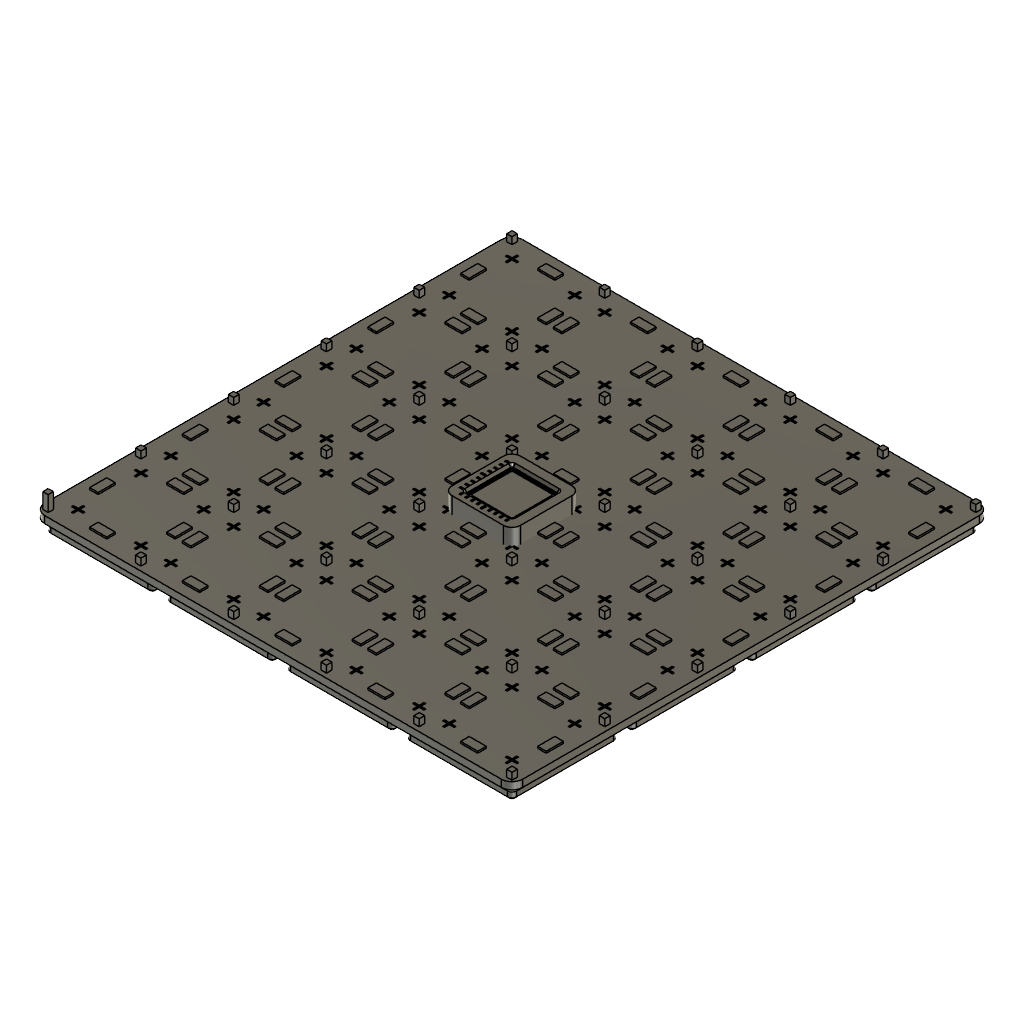
da-lab3-tilgaplaat-atoms3-mudel (Autodesk Fusion 360 design; units mm, degrees)
part number: 2026-11-13-17-36-51-627
part number: 2026-11-13-17-36-56-494
part number: 2026-11-13-17-37-25-971
Autodesk Fusion 360 part; units mm, degrees
(part 1 of 3)
ref_plane "WorkPlane1" through (0, 0, 4.75) normal (0, 0, 1) x (1, 0, 0) in component "drop_plate"
sketch "plate" plane through (0, 0, 4.75) normal (0, 0, 1) x (1, 0, 0) in component "drop_plate"
  line L0 (-80, -83.75) -> (80, -83.75)
  line L1 (83.75, -80) -> (83.75, 80)
  line L2 (80, 83.75) -> (-80, 83.75)
  line L3 (-83.75, 80) -> (-83.75, -80)
  arc A0 (80, -83.75) -> (83.75, -80) centre (80, -80) ccw
  arc A1 (83.75, 80) -> (80, 83.75) centre (80, 80) ccw
  arc A2 (-80, 83.75) -> (-83.75, 80) centre (-80, 80) ccw
  arc A3 (-83.75, -80) -> (-80, -83.75) centre (-80, -80) ccw
  constraint tangent L0 A0
  constraint tangent L1 A0
  constraint tangent L1 A1
  constraint tangent L2 A1
  constraint tangent L2 A2
  constraint tangent L3 A2
  constraint tangent L3 A3
  constraint tangent L0 A3
extrude "plate (1)" add sketch "plate" along normal blind 2.5 makes body 1 in component "drop_plate"
ref_plane "WorkPlane2" through (0, 0, 4.75) normal (0, 0, 1) x (1, 0, 0) in component "drop_plate"
sketch "gf_std_foot1" plane through (0, 0, 4.75) normal (0, 0, 1) x (1, 0, 0) in component "drop_plate"
  line L0 (-46, -42.25) -> (-80, -42.25)
  line L1 (-83.75, -46) -> (-83.75, -80)
  line L2 (-80, -83.75) -> (-46, -83.75)
  line L3 (-42.25, -80) -> (-42.25, -46)
  arc A0 (-80, -42.25) -> (-83.75, -46) centre (-80, -46) ccw
  arc A1 (-83.75, -80) -> (-80, -83.75) centre (-80, -80) ccw
  arc A2 (-46, -83.75) -> (-42.25, -80) centre (-46, -80) ccw
  arc A3 (-42.25, -46) -> (-46, -42.25) centre (-46, -46) ccw
  line L4 (-46, -0.25) -> (-80, -0.25)
  line L5 (-83.75, -4) -> (-83.75, -38)
  line L6 (-80, -41.75) -> (-46, -41.75)
  line L7 (-42.25, -38) -> (-42.25, -4)
  arc A4 (-80, -0.25) -> (-83.75, -4) centre (-80, -4) ccw
  arc A5 (-83.75, -38) -> (-80, -41.75) centre (-80, -38) ccw
  arc A6 (-46, -41.75) -> (-42.25, -38) centre (-46, -38) ccw
  arc A7 (-42.25, -4) -> (-46, -0.25) centre (-46, -4) ccw
  line L8 (-46, 41.75) -> (-80, 41.75)
  line L9 (-83.75, 38) -> (-83.75, 4)
  line L10 (-80, 0.25) -> (-46, 0.25)
  line L11 (-42.25, 4) -> (-42.25, 38)
  arc A8 (-80, 41.75) -> (-83.75, 38) centre (-80, 38) ccw
  arc A9 (-83.75, 4) -> (-80, 0.25) centre (-80, 4) ccw
  arc A10 (-46, 0.25) -> (-42.25, 4) centre (-46, 4) ccw
  arc A11 (-42.25, 38) -> (-46, 41.75) centre (-46, 38) ccw
  line L12 (-46, 83.75) -> (-80, 83.75)
  line L13 (-83.75, 80) -> (-83.75, 46)
  line L14 (-80, 42.25) -> (-46, 42.25)
  line L15 (-42.25, 46) -> (-42.25, 80)
  arc A12 (-80, 83.75) -> (-83.75, 80) centre (-80, 80) ccw
  arc A13 (-83.75, 46) -> (-80, 42.25) centre (-80, 46) ccw
  arc A14 (-46, 42.25) -> (-42.25, 46) centre (-46, 46) ccw
  arc A15 (-42.25, 80) -> (-46, 83.75) centre (-46, 80) ccw
  line L16 (-4, -42.25) -> (-38, -42.25)
  line L17 (-41.75, -46) -> (-41.75, -80)
  line L18 (-38, -83.75) -> (-4, -83.75)
  line L19 (-0.25, -80) -> (-0.25, -46)
  arc A16 (-38, -42.25) -> (-41.75, -46) centre (-38, -46) ccw
  arc A17 (-41.75, -80) -> (-38, -83.75) centre (-38, -80) ccw
  arc A18 (-4, -83.75) -> (-0.25, -80) centre (-4, -80) ccw
  arc A19 (-0.25, -46) -> (-4, -42.25) centre (-4, -46) ccw
  line L20 (-4, -0.25) -> (-38, -0.25)
  line L21 (-41.75, -4) -> (-41.75, -38)
  line L22 (-38, -41.75) -> (-4, -41.75)
  line L23 (-0.25, -38) -> (-0.25, -4)
  arc A20 (-38, -0.25) -> (-41.75, -4) centre (-38, -4) ccw
  arc A21 (-41.75, -38) -> (-38, -41.75) centre (-38, -38) ccw
  arc A22 (-4, -41.75) -> (-0.25, -38) centre (-4, -38) ccw
  arc A23 (-0.25, -4) -> (-4, -0.25) centre (-4, -4) ccw
  line L24 (-4, 41.75) -> (-38, 41.75)
  line L25 (-41.75, 38) -> (-41.75, 4)
  line L26 (-38, 0.25) -> (-4, 0.25)
  line L27 (-0.25, 4) -> (-0.25, 38)
  arc A24 (-38, 41.75) -> (-41.75, 38) centre (-38, 38) ccw
  arc A25 (-41.75, 4) -> (-38, 0.25) centre (-38, 4) ccw
  arc A26 (-4, 0.25) -> (-0.25, 4) centre (-4, 4) ccw
  arc A27 (-0.25, 38) -> (-4, 41.75) centre (-4, 38) ccw
  line L28 (-4, 83.75) -> (-38, 83.75)
  line L29 (-41.75, 80) -> (-41.75, 46)
  line L30 (-38, 42.25) -> (-4, 42.25)
  line L31 (-0.25, 46) -> (-0.25, 80)
  arc A28 (-38, 83.75) -> (-41.75, 80) centre (-38, 80) ccw
  arc A29 (-41.75, 46) -> (-38, 42.25) centre (-38, 46) ccw
  arc A30 (-4, 42.25) -> (-0.25, 46) centre (-4, 46) ccw
  arc A31 (-0.25, 80) -> (-4, 83.75) centre (-4, 80) ccw
  line L32 (38, -42.25) -> (4, -42.25)
  line L33 (0.25, -46) -> (0.25, -80)
  line L34 (4, -83.75) -> (38, -83.75)
  line L35 (41.75, -80) -> (41.75, -46)
  arc A32 (4, -42.25) -> (0.25, -46) centre (4, -46) ccw
  arc A33 (0.25, -80) -> (4, -83.75) centre (4, -80) ccw
  arc A34 (38, -83.75) -> (41.75, -80) centre (38, -80) ccw
  arc A35 (41.75, -46) -> (38, -42.25) centre (38, -46) ccw
  line L36 (38, -0.25) -> (4, -0.25)
  line L37 (0.25, -4) -> (0.25, -38)
  line L38 (4, -41.75) -> (38, -41.75)
  line L39 (41.75, -38) -> (41.75, -4)
  arc A36 (4, -0.25) -> (0.25, -4) centre (4, -4) ccw
  arc A37 (0.25, -38) -> (4, -41.75) centre (4, -38) ccw
  arc A38 (38, -41.75) -> (41.75, -38) centre (38, -38) ccw
  arc A39 (41.75, -4) -> (38, -0.25) centre (38, -4) ccw
  line L40 (38, 41.75) -> (4, 41.75)
  line L41 (0.25, 38) -> (0.25, 4)
  line L42 (4, 0.25) -> (38, 0.25)
  line L43 (41.75, 4) -> (41.75, 38)
  arc A40 (4, 41.75) -> (0.25, 38) centre (4, 38) ccw
  arc A41 (0.25, 4) -> (4, 0.25) centre (4, 4) ccw
  arc A42 (38, 0.25) -> (41.75, 4) centre (38, 4) ccw
  arc A43 (41.75, 38) -> (38, 41.75) centre (38, 38) ccw
  line L44 (38, 83.75) -> (4, 83.75)
  line L45 (0.25, 80) -> (0.25, 46)
  line L46 (4, 42.25) -> (38, 42.25)
  line L47 (41.75, 46) -> (41.75, 80)
  arc A44 (4, 83.75) -> (0.25, 80) centre (4, 80) ccw
  arc A45 (0.25, 46) -> (4, 42.25) centre (4, 46) ccw
  arc A46 (38, 42.25) -> (41.75, 46) centre (38, 46) ccw
  arc A47 (41.75, 80) -> (38, 83.75) centre (38, 80) ccw
  line L48 (80, -42.25) -> (46, -42.25)
  line L49 (42.25, -46) -> (42.25, -80)
  line L50 (46, -83.75) -> (80, -83.75)
  line L51 (83.75, -80) -> (83.75, -46)
  arc A48 (46, -42.25) -> (42.25, -46) centre (46, -46) ccw
  arc A49 (42.25, -80) -> (46, -83.75) centre (46, -80) ccw
  arc A50 (80, -83.75) -> (83.75, -80) centre (80, -80) ccw
  arc A51 (83.75, -46) -> (80, -42.25) centre (80, -46) ccw
  line L52 (80, -0.25) -> (46, -0.25)
  line L53 (42.25, -4) -> (42.25, -38)
  line L54 (46, -41.75) -> (80, -41.75)
  line L55 (83.75, -38) -> (83.75, -4)
  arc A52 (46, -0.25) -> (42.25, -4) centre (46, -4) ccw
  arc A53 (42.25, -38) -> (46, -41.75) centre (46, -38) ccw
  arc A54 (80, -41.75) -> (83.75, -38) centre (80, -38) ccw
  arc A55 (83.75, -4) -> (80, -0.25) centre (80, -4) ccw
  line L56 (80, 41.75) -> (46, 41.75)
  line L57 (42.25, 38) -> (42.25, 4)
  line L58 (46, 0.25) -> (80, 0.25)
  line L59 (83.75, 4) -> (83.75, 38)
  arc A56 (46, 41.75) -> (42.25, 38) centre (46, 38) ccw
  arc A57 (42.25, 4) -> (46, 0.25) centre (46, 4) ccw
  arc A58 (80, 0.25) -> (83.75, 4) centre (80, 4) ccw
  arc A59 (83.75, 38) -> (80, 41.75) centre (80, 38) ccw
  line L60 (80, 83.75) -> (46, 83.75)
  line L61 (42.25, 80) -> (42.25, 46)
  line L62 (46, 42.25) -> (80, 42.25)
  line L63 (83.75, 46) -> (83.75, 80)
  arc A60 (46, 83.75) -> (42.25, 80) centre (46, 80) ccw
  arc A61 (42.25, 46) -> (46, 42.25) centre (46, 46) ccw
  arc A62 (80, 42.25) -> (83.75, 46) centre (80, 46) ccw
  arc A63 (83.75, 80) -> (80, 83.75) centre (80, 80) ccw
  constraint tangent L0 A0
  constraint tangent L1 A0
  constraint tangent L1 A1
  constraint tangent L2 A1
  constraint tangent L2 A2
  constraint tangent L3 A2
  constraint tangent L3 A3
  constraint tangent L0 A3
  constraint tangent L4 A4
  constraint tangent L5 A4
  constraint tangent L5 A5
  constraint tangent L6 A5
  constraint tangent L6 A6
  constraint tangent L7 A6
  constraint tangent L7 A7
  constraint tangent L4 A7
  constraint tangent L8 A8
  constraint tangent L9 A8
  constraint tangent L9 A9
  constraint tangent L10 A9
  constraint tangent L10 A10
  constraint tangent L11 A10
  constraint tangent L11 A11
  constraint tangent L8 A11
  constraint tangent L12 A12
  constraint tangent L13 A12
  constraint tangent L13 A13
  constraint tangent L14 A13
  constraint tangent L14 A14
  constraint tangent L15 A14
  constraint tangent L15 A15
  constraint tangent L12 A15
  constraint tangent L16 A16
  constraint tangent L17 A16
  constraint tangent L17 A17
  constraint tangent L18 A17
  constraint tangent L18 A18
  constraint tangent L19 A18
  constraint tangent L19 A19
  constraint tangent L16 A19
  constraint tangent L20 A20
  constraint tangent L21 A20
  constraint tangent L21 A21
  constraint tangent L22 A21
  constraint tangent L22 A22
  constraint tangent L23 A22
  constraint tangent L23 A23
  constraint tangent L20 A23
  constraint tangent L24 A24
  constraint tangent L25 A24
  constraint tangent L25 A25
  constraint tangent L26 A25
  constraint tangent L26 A26
  constraint tangent L27 A26
  constraint tangent L27 A27
  constraint tangent L24 A27
  constraint tangent L28 A28
  constraint tangent L29 A28
  constraint tangent L29 A29
  constraint tangent L30 A29
  constraint tangent L30 A30
  constraint tangent L31 A30
  constraint tangent L31 A31
  constraint tangent L28 A31
  constraint tangent L32 A32
  constraint tangent L33 A32
  constraint tangent L33 A33
  constraint tangent L34 A33
  constraint tangent L34 A34
  constraint tangent L35 A34
  constraint tangent L35 A35
  constraint tangent L32 A35
  constraint tangent L36 A36
  constraint tangent L37 A36
  constraint tangent L37 A37
  constraint tangent L38 A37
  constraint tangent L38 A38
  constraint tangent L39 A38
  constraint tangent L39 A39
  constraint tangent L36 A39
  constraint tangent L40 A40
  constraint tangent L41 A40
  constraint tangent L41 A41
  constraint tangent L42 A41
  constraint tangent L42 A42
  constraint tangent L43 A42
  constraint tangent L43 A43
  constraint tangent L40 A43
  constraint tangent L44 A44
  constraint tangent L45 A44
  constraint tangent L45 A45
  constraint tangent L46 A45
  constraint tangent L46 A46
  constraint tangent L47 A46
  constraint tangent L47 A47
  constraint tangent L44 A47
  constraint tangent L48 A48
  constraint tangent L49 A48
  constraint tangent L49 A49
  constraint tangent L50 A49
  constraint tangent L50 A50
  constraint tangent L51 A50
  constraint tangent L51 A51
  constraint tangent L48 A51
  constraint tangent L52 A52
  constraint tangent L53 A52
  constraint tangent L53 A53
  constraint tangent L54 A53
  constraint tangent L54 A54
  constraint tangent L55 A54
  constraint tangent L55 A55
  constraint tangent L52 A55
  constraint tangent L56 A56
  constraint tangent L57 A56
  constraint tangent L57 A57
  constraint tangent L58 A57
  constraint tangent L58 A58
  constraint tangent L59 A58
  constraint tangent L59 A59
  constraint tangent L56 A59
  constraint tangent L60 A60
  constraint tangent L61 A60
  constraint tangent L61 A61
  constraint tangent L62 A61
  constraint tangent L62 A62
  constraint tangent L63 A62
  constraint tangent L63 A63
  constraint tangent L60 A63
extrude "gf_std_foot1 (1)" add sketch "gf_std_foot1" against normal blind 2.15 draft -45 bodies 1 in component "drop_plate"
ref_plane "WorkPlane3" through (0, 0, 2.6) normal (0, 0, 1) x (1, 0, 0) in component "drop_plate"
sketch "gf_std_foot2" plane through (0, 0, 2.6) normal (0, 0, 1) x (1, 0, 0) in component "drop_plate"
  line L0 (-46, -44.4) -> (-80, -44.4)
  line L1 (-81.6, -46) -> (-81.6, -80)
  line L2 (-80, -81.6) -> (-46, -81.6)
  line L3 (-44.4, -80) -> (-44.4, -46)
  arc A0 (-80, -44.4) -> (-81.6, -46) centre (-80, -46) ccw
  arc A1 (-81.6, -80) -> (-80, -81.6) centre (-80, -80) ccw
  arc A2 (-46, -81.6) -> (-44.4, -80) centre (-46, -80) ccw
  arc A3 (-44.4, -46) -> (-46, -44.4) centre (-46, -46) ccw
  line L4 (-46, -2.4) -> (-80, -2.4)
  line L5 (-81.6, -4) -> (-81.6, -38)
  line L6 (-80, -39.6) -> (-46, -39.6)
  line L7 (-44.4, -38) -> (-44.4, -4)
  arc A4 (-80, -2.4) -> (-81.6, -4) centre (-80, -4) ccw
  arc A5 (-81.6, -38) -> (-80, -39.6) centre (-80, -38) ccw
  arc A6 (-46, -39.6) -> (-44.4, -38) centre (-46, -38) ccw
  arc A7 (-44.4, -4) -> (-46, -2.4) centre (-46, -4) ccw
  line L8 (-46, 39.6) -> (-80, 39.6)
  line L9 (-81.6, 38) -> (-81.6, 4)
  line L10 (-80, 2.4) -> (-46, 2.4)
  line L11 (-44.4, 4) -> (-44.4, 38)
  arc A8 (-80, 39.6) -> (-81.6, 38) centre (-80, 38) ccw
  arc A9 (-81.6, 4) -> (-80, 2.4) centre (-80, 4) ccw
  arc A10 (-46, 2.4) -> (-44.4, 4) centre (-46, 4) ccw
  arc A11 (-44.4, 38) -> (-46, 39.6) centre (-46, 38) ccw
  line L12 (-46, 81.6) -> (-80, 81.6)
  line L13 (-81.6, 80) -> (-81.6, 46)
  line L14 (-80, 44.4) -> (-46, 44.4)
  line L15 (-44.4, 46) -> (-44.4, 80)
  arc A12 (-80, 81.6) -> (-81.6, 80) centre (-80, 80) ccw
  arc A13 (-81.6, 46) -> (-80, 44.4) centre (-80, 46) ccw
  arc A14 (-46, 44.4) -> (-44.4, 46) centre (-46, 46) ccw
  arc A15 (-44.4, 80) -> (-46, 81.6) centre (-46, 80) ccw
  line L16 (-4, -44.4) -> (-38, -44.4)
  line L17 (-39.6, -46) -> (-39.6, -80)
  line L18 (-38, -81.6) -> (-4, -81.6)
  line L19 (-2.4, -80) -> (-2.4, -46)
  arc A16 (-38, -44.4) -> (-39.6, -46) centre (-38, -46) ccw
  arc A17 (-39.6, -80) -> (-38, -81.6) centre (-38, -80) ccw
  arc A18 (-4, -81.6) -> (-2.4, -80) centre (-4, -80) ccw
  arc A19 (-2.4, -46) -> (-4, -44.4) centre (-4, -46) ccw
  line L20 (-4, -2.4) -> (-38, -2.4)
  line L21 (-39.6, -4) -> (-39.6, -38)
  line L22 (-38, -39.6) -> (-4, -39.6)
  line L23 (-2.4, -38) -> (-2.4, -4)
  arc A20 (-38, -2.4) -> (-39.6, -4) centre (-38, -4) ccw
  arc A21 (-39.6, -38) -> (-38, -39.6) centre (-38, -38) ccw
  arc A22 (-4, -39.6) -> (-2.4, -38) centre (-4, -38) ccw
  arc A23 (-2.4, -4) -> (-4, -2.4) centre (-4, -4) ccw
  line L24 (-4, 39.6) -> (-38, 39.6)
  line L25 (-39.6, 38) -> (-39.6, 4)
  line L26 (-38, 2.4) -> (-4, 2.4)
  line L27 (-2.4, 4) -> (-2.4, 38)
  arc A24 (-38, 39.6) -> (-39.6, 38) centre (-38, 38) ccw
  arc A25 (-39.6, 4) -> (-38, 2.4) centre (-38, 4) ccw
  arc A26 (-4, 2.4) -> (-2.4, 4) centre (-4, 4) ccw
  arc A27 (-2.4, 38) -> (-4, 39.6) centre (-4, 38) ccw
  line L28 (-4, 81.6) -> (-38, 81.6)
  line L29 (-39.6, 80) -> (-39.6, 46)
  line L30 (-38, 44.4) -> (-4, 44.4)
  line L31 (-2.4, 46) -> (-2.4, 80)
  arc A28 (-38, 81.6) -> (-39.6, 80) centre (-38, 80) ccw
  arc A29 (-39.6, 46) -> (-38, 44.4) centre (-38, 46) ccw
  arc A30 (-4, 44.4) -> (-2.4, 46) centre (-4, 46) ccw
  arc A31 (-2.4, 80) -> (-4, 81.6) centre (-4, 80) ccw
  line L32 (38, -44.4) -> (4, -44.4)
  line L33 (2.4, -46) -> (2.4, -80)
  line L34 (4, -81.6) -> (38, -81.6)
  line L35 (39.6, -80) -> (39.6, -46)
  arc A32 (4, -44.4) -> (2.4, -46) centre (4, -46) ccw
  arc A33 (2.4, -80) -> (4, -81.6) centre (4, -80) ccw
  arc A34 (38, -81.6) -> (39.6, -80) centre (38, -80) ccw
  arc A35 (39.6, -46) -> (38, -44.4) centre (38, -46) ccw
  line L36 (38, -2.4) -> (4, -2.4)
  line L37 (2.4, -4) -> (2.4, -38)
  line L38 (4, -39.6) -> (38, -39.6)
  line L39 (39.6, -38) -> (39.6, -4)
  arc A36 (4, -2.4) -> (2.4, -4) centre (4, -4) ccw
  arc A37 (2.4, -38) -> (4, -39.6) centre (4, -38) ccw
  arc A38 (38, -39.6) -> (39.6, -38) centre (38, -38) ccw
  arc A39 (39.6, -4) -> (38, -2.4) centre (38, -4) ccw
  line L40 (38, 39.6) -> (4, 39.6)
  line L41 (2.4, 38) -> (2.4, 4)
  line L42 (4, 2.4) -> (38, 2.4)
  line L43 (39.6, 4) -> (39.6, 38)
  arc A40 (4, 39.6) -> (2.4, 38) centre (4, 38) ccw
  arc A41 (2.4, 4) -> (4, 2.4) centre (4, 4) ccw
  arc A42 (38, 2.4) -> (39.6, 4) centre (38, 4) ccw
  arc A43 (39.6, 38) -> (38, 39.6) centre (38, 38) ccw
  line L44 (38, 81.6) -> (4, 81.6)
  line L45 (2.4, 80) -> (2.4, 46)
  line L46 (4, 44.4) -> (38, 44.4)
  line L47 (39.6, 46) -> (39.6, 80)
  arc A44 (4, 81.6) -> (2.4, 80) centre (4, 80) ccw
  arc A45 (2.4, 46) -> (4, 44.4) centre (4, 46) ccw
  arc A46 (38, 44.4) -> (39.6, 46) centre (38, 46) ccw
  arc A47 (39.6, 80) -> (38, 81.6) centre (38, 80) ccw
  line L48 (80, -44.4) -> (46, -44.4)
  line L49 (44.4, -46) -> (44.4, -80)
  line L50 (46, -81.6) -> (80, -81.6)
  line L51 (81.6, -80) -> (81.6, -46)
  arc A48 (46, -44.4) -> (44.4, -46) centre (46, -46) ccw
  arc A49 (44.4, -80) -> (46, -81.6) centre (46, -80) ccw
  arc A50 (80, -81.6) -> (81.6, -80) centre (80, -80) ccw
  arc A51 (81.6, -46) -> (80, -44.4) centre (80, -46) ccw
  line L52 (80, -2.4) -> (46, -2.4)
  line L53 (44.4, -4) -> (44.4, -38)
  line L54 (46, -39.6) -> (80, -39.6)
  line L55 (81.6, -38) -> (81.6, -4)
  arc A52 (46, -2.4) -> (44.4, -4) centre (46, -4) ccw
  arc A53 (44.4, -38) -> (46, -39.6) centre (46, -38) ccw
  arc A54 (80, -39.6) -> (81.6, -38) centre (80, -38) ccw
  arc A55 (81.6, -4) -> (80, -2.4) centre (80, -4) ccw
  line L56 (80, 39.6) -> (46, 39.6)
  line L57 (44.4, 38) -> (44.4, 4)
  line L58 (46, 2.4) -> (80, 2.4)
  line L59 (81.6, 4) -> (81.6, 38)
  arc A56 (46, 39.6) -> (44.4, 38) centre (46, 38) ccw
  arc A57 (44.4, 4) -> (46, 2.4) centre (46, 4) ccw
  arc A58 (80, 2.4) -> (81.6, 4) centre (80, 4) ccw
  arc A59 (81.6, 38) -> (80, 39.6) centre (80, 38) ccw
  line L60 (80, 81.6) -> (46, 81.6)
  line L61 (44.4, 80) -> (44.4, 46)
  line L62 (46, 44.4) -> (80, 44.4)
  line L63 (81.6, 46) -> (81.6, 80)
  arc A60 (46, 81.6) -> (44.4, 80) centre (46, 80) ccw
  arc A61 (44.4, 46) -> (46, 44.4) centre (46, 46) ccw
  arc A62 (80, 44.4) -> (81.6, 46) centre (80, 46) ccw
  arc A63 (81.6, 80) -> (80, 81.6) centre (80, 80) ccw
  constraint tangent L0 A0
  constraint tangent L1 A0
  constraint tangent L1 A1
  constraint tangent L2 A1
  constraint tangent L2 A2
  constraint tangent L3 A2
  constraint tangent L3 A3
  constraint tangent L0 A3
  constraint tangent L4 A4
  constraint tangent L5 A4
  constraint tangent L5 A5
  constraint tangent L6 A5
  constraint tangent L6 A6
  constraint tangent L7 A6
  constraint tangent L7 A7
  constraint tangent L4 A7
  constraint tangent L8 A8
  constraint tangent L9 A8
  constraint tangent L9 A9
  constraint tangent L10 A9
  constraint tangent L10 A10
  constraint tangent L11 A10
  constraint tangent L11 A11
  constraint tangent L8 A11
  constraint tangent L12 A12
  constraint tangent L13 A12
  constraint tangent L13 A13
  constraint tangent L14 A13
  constraint tangent L14 A14
  constraint tangent L15 A14
  constraint tangent L15 A15
  constraint tangent L12 A15
  constraint tangent L16 A16
  constraint tangent L17 A16
  constraint tangent L17 A17
  constraint tangent L18 A17
  constraint tangent L18 A18
  constraint tangent L19 A18
  constraint tangent L19 A19
  constraint tangent L16 A19
  constraint tangent L20 A20
  constraint tangent L21 A20
  constraint tangent L21 A21
  constraint tangent L22 A21
  constraint tangent L22 A22
  constraint tangent L23 A22
  constraint tangent L23 A23
  constraint tangent L20 A23
  constraint tangent L24 A24
  constraint tangent L25 A24
  constraint tangent L25 A25
  constraint tangent L26 A25
  constraint tangent L26 A26
  constraint tangent L27 A26
  constraint tangent L27 A27
  constraint tangent L24 A27
  constraint tangent L28 A28
  constraint tangent L29 A28
  constraint tangent L29 A29
  constraint tangent L30 A29
  constraint tangent L30 A30
  constraint tangent L31 A30
  constraint tangent L31 A31
  constraint tangent L28 A31
  constraint tangent L32 A32
  constraint tangent L33 A32
  constraint tangent L33 A33
  constraint tangent L34 A33
  constraint tangent L34 A34
  constraint tangent L35 A34
  constraint tangent L35 A35
  constraint tangent L32 A35
  constraint tangent L36 A36
  constraint tangent L37 A36
  constraint tangent L37 A37
  constraint tangent L38 A37
  constraint tangent L38 A38
  constraint tangent L39 A38
  constraint tangent L39 A39
  constraint tangent L36 A39
  constraint tangent L40 A40
  constraint tangent L41 A40
  constraint tangent L41 A41
  constraint tangent L42 A41
  constraint tangent L42 A42
  constraint tangent L43 A42
  constraint tangent L43 A43
  constraint tangent L40 A43
  constraint tangent L44 A44
  constraint tangent L45 A44
  constraint tangent L45 A45
  constraint tangent L46 A45
  constraint tangent L46 A46
  constraint tangent L47 A46
  constraint tangent L47 A47
  constraint tangent L44 A47
  constraint tangent L48 A48
  constraint tangent L49 A48
  constraint tangent L49 A49
  constraint tangent L50 A49
  constraint tangent L50 A50
  constraint tangent L51 A50
  constraint tangent L51 A51
  constraint tangent L48 A51
  constraint tangent L52 A52
  constraint tangent L53 A52
  constraint tangent L53 A53
  constraint tangent L54 A53
  constraint tangent L54 A54
  constraint tangent L55 A54
  constraint tangent L55 A55
  constraint tangent L52 A55
  constraint tangent L56 A56
  constraint tangent L57 A56
  constraint tangent L57 A57
  constraint tangent L58 A57
  constraint tangent L58 A58
  constraint tangent L59 A58
  constraint tangent L59 A59
  constraint tangent L56 A59
  constraint tangent L60 A60
  constraint tangent L61 A60
  constraint tangent L61 A61
  constraint tangent L62 A61
  constraint tangent L62 A62
  constraint tangent L63 A62
  constraint tangent L63 A63
  constraint tangent L60 A63
extrude "gf_std_foot2 (1)" add sketch "gf_std_foot2" against normal blind 1.8 bodies 1 in component "drop_plate"
ref_plane "WorkPlane4" through (0, 0, 0.8) normal (0, 0, 1) x (1, 0, 0) in component "drop_plate"
sketch "gf_std_foot3" plane through (0, 0, 0.8) normal (0, 0, 1) x (1, 0, 0) in component "drop_plate"
  line L0 (-46, -44.4) -> (-80, -44.4)
  line L1 (-81.6, -46) -> (-81.6, -80)
  line L2 (-80, -81.6) -> (-46, -81.6)
  line L3 (-44.4, -80) -> (-44.4, -46)
  arc A0 (-80, -44.4) -> (-81.6, -46) centre (-80, -46) ccw
  arc A1 (-81.6, -80) -> (-80, -81.6) centre (-80, -80) ccw
  arc A2 (-46, -81.6) -> (-44.4, -80) centre (-46, -80) ccw
  arc A3 (-44.4, -46) -> (-46, -44.4) centre (-46, -46) ccw
  line L4 (-46, -2.4) -> (-80, -2.4)
  line L5 (-81.6, -4) -> (-81.6, -38)
  line L6 (-80, -39.6) -> (-46, -39.6)
  line L7 (-44.4, -38) -> (-44.4, -4)
  arc A4 (-80, -2.4) -> (-81.6, -4) centre (-80, -4) ccw
  arc A5 (-81.6, -38) -> (-80, -39.6) centre (-80, -38) ccw
  arc A6 (-46, -39.6) -> (-44.4, -38) centre (-46, -38) ccw
  arc A7 (-44.4, -4) -> (-46, -2.4) centre (-46, -4) ccw
  line L8 (-46, 39.6) -> (-80, 39.6)
  line L9 (-81.6, 38) -> (-81.6, 4)
  line L10 (-80, 2.4) -> (-46, 2.4)
  line L11 (-44.4, 4) -> (-44.4, 38)
  arc A8 (-80, 39.6) -> (-81.6, 38) centre (-80, 38) ccw
  arc A9 (-81.6, 4) -> (-80, 2.4) centre (-80, 4) ccw
  arc A10 (-46, 2.4) -> (-44.4, 4) centre (-46, 4) ccw
  arc A11 (-44.4, 38) -> (-46, 39.6) centre (-46, 38) ccw
  line L12 (-46, 81.6) -> (-80, 81.6)
  line L13 (-81.6, 80) -> (-81.6, 46)
  line L14 (-80, 44.4) -> (-46, 44.4)
  line L15 (-44.4, 46) -> (-44.4, 80)
  arc A12 (-80, 81.6) -> (-81.6, 80) centre (-80, 80) ccw
  arc A13 (-81.6, 46) -> (-80, 44.4) centre (-80, 46) ccw
  arc A14 (-46, 44.4) -> (-44.4, 46) centre (-46, 46) ccw
  arc A15 (-44.4, 80) -> (-46, 81.6) centre (-46, 80) ccw
  line L16 (-4, -44.4) -> (-38, -44.4)
  line L17 (-39.6, -46) -> (-39.6, -80)
  line L18 (-38, -81.6) -> (-4, -81.6)
  line L19 (-2.4, -80) -> (-2.4, -46)
  arc A16 (-38, -44.4) -> (-39.6, -46) centre (-38, -46) ccw
  arc A17 (-39.6, -80) -> (-38, -81.6) centre (-38, -80) ccw
  arc A18 (-4, -81.6) -> (-2.4, -80) centre (-4, -80) ccw
  arc A19 (-2.4, -46) -> (-4, -44.4) centre (-4, -46) ccw
  line L20 (-4, -2.4) -> (-38, -2.4)
  line L21 (-39.6, -4) -> (-39.6, -38)
  line L22 (-38, -39.6) -> (-4, -39.6)
  line L23 (-2.4, -38) -> (-2.4, -4)
  arc A20 (-38, -2.4) -> (-39.6, -4) centre (-38, -4) ccw
  arc A21 (-39.6, -38) -> (-38, -39.6) centre (-38, -38) ccw
  arc A22 (-4, -39.6) -> (-2.4, -38) centre (-4, -38) ccw
  arc A23 (-2.4, -4) -> (-4, -2.4) centre (-4, -4) ccw
  line L24 (-4, 39.6) -> (-38, 39.6)
  line L25 (-39.6, 38) -> (-39.6, 4)
  line L26 (-38, 2.4) -> (-4, 2.4)
  line L27 (-2.4, 4) -> (-2.4, 38)
  arc A24 (-38, 39.6) -> (-39.6, 38) centre (-38, 38) ccw
  arc A25 (-39.6, 4) -> (-38, 2.4) centre (-38, 4) ccw
  arc A26 (-4, 2.4) -> (-2.4, 4) centre (-4, 4) ccw
  arc A27 (-2.4, 38) -> (-4, 39.6) centre (-4, 38) ccw
  line L28 (-4, 81.6) -> (-38, 81.6)
  line L29 (-39.6, 80) -> (-39.6, 46)
  line L30 (-38, 44.4) -> (-4, 44.4)
  line L31 (-2.4, 46) -> (-2.4, 80)
  arc A28 (-38, 81.6) -> (-39.6, 80) centre (-38, 80) ccw
  arc A29 (-39.6, 46) -> (-38, 44.4) centre (-38, 46) ccw
  arc A30 (-4, 44.4) -> (-2.4, 46) centre (-4, 46) ccw
  arc A31 (-2.4, 80) -> (-4, 81.6) centre (-4, 80) ccw
  line L32 (38, -44.4) -> (4, -44.4)
  line L33 (2.4, -46) -> (2.4, -80)
  line L34 (4, -81.6) -> (38, -81.6)
  line L35 (39.6, -80) -> (39.6, -46)
  arc A32 (4, -44.4) -> (2.4, -46) centre (4, -46) ccw
  arc A33 (2.4, -80) -> (4, -81.6) centre (4, -80) ccw
  arc A34 (38, -81.6) -> (39.6, -80) centre (38, -80) ccw
  arc A35 (39.6, -46) -> (38, -44.4) centre (38, -46) ccw
  line L36 (38, -2.4) -> (4, -2.4)
  line L37 (2.4, -4) -> (2.4, -38)
  line L38 (4, -39.6) -> (38, -39.6)
  line L39 (39.6, -38) -> (39.6, -4)
  arc A36 (4, -2.4) -> (2.4, -4) centre (4, -4) ccw
  arc A37 (2.4, -38) -> (4, -39.6) centre (4, -38) ccw
  arc A38 (38, -39.6) -> (39.6, -38) centre (38, -38) ccw
  arc A39 (39.6, -4) -> (38, -2.4) centre (38, -4) ccw
  line L40 (38, 39.6) -> (4, 39.6)
  line L41 (2.4, 38) -> (2.4, 4)
  line L42 (4, 2.4) -> (38, 2.4)
  line L43 (39.6, 4) -> (39.6, 38)
  arc A40 (4, 39.6) -> (2.4, 38) centre (4, 38) ccw
  arc A41 (2.4, 4) -> (4, 2.4) centre (4, 4) ccw
  arc A42 (38, 2.4) -> (39.6, 4) centre (38, 4) ccw
  arc A43 (39.6, 38) -> (38, 39.6) centre (38, 38) ccw
  line L44 (38, 81.6) -> (4, 81.6)
  line L45 (2.4, 80) -> (2.4, 46)
  line L46 (4, 44.4) -> (38, 44.4)
  line L47 (39.6, 46) -> (39.6, 80)
  arc A44 (4, 81.6) -> (2.4, 80) centre (4, 80) ccw
  arc A45 (2.4, 46) -> (4, 44.4) centre (4, 46) ccw
  arc A46 (38, 44.4) -> (39.6, 46) centre (38, 46) ccw
  arc A47 (39.6, 80) -> (38, 81.6) centre (38, 80) ccw
  line L48 (80, -44.4) -> (46, -44.4)
  line L49 (44.4, -46) -> (44.4, -80)
  line L50 (46, -81.6) -> (80, -81.6)
  line L51 (81.6, -80) -> (81.6, -46)
  arc A48 (46, -44.4) -> (44.4, -46) centre (46, -46) ccw
  arc A49 (44.4, -80) -> (46, -81.6) centre (46, -80) ccw
  arc A50 (80, -81.6) -> (81.6, -80) centre (80, -80) ccw
  arc A51 (81.6, -46) -> (80, -44.4) centre (80, -46) ccw
  line L52 (80, -2.4) -> (46, -2.4)
  line L53 (44.4, -4) -> (44.4, -38)
  line L54 (46, -39.6) -> (80, -39.6)
  line L55 (81.6, -38) -> (81.6, -4)
  arc A52 (46, -2.4) -> (44.4, -4) centre (46, -4) ccw
  arc A53 (44.4, -38) -> (46, -39.6) centre (46, -38) ccw
  arc A54 (80, -39.6) -> (81.6, -38) centre (80, -38) ccw
  arc A55 (81.6, -4) -> (80, -2.4) centre (80, -4) ccw
  line L56 (80, 39.6) -> (46, 39.6)
  line L57 (44.4, 38) -> (44.4, 4)
  line L58 (46, 2.4) -> (80, 2.4)
  line L59 (81.6, 4) -> (81.6, 38)
  arc A56 (46, 39.6) -> (44.4, 38) centre (46, 38) ccw
  arc A57 (44.4, 4) -> (46, 2.4) centre (46, 4) ccw
  arc A58 (80, 2.4) -> (81.6, 4) centre (80, 4) ccw
  arc A59 (81.6, 38) -> (80, 39.6) centre (80, 38) ccw
  line L60 (80, 81.6) -> (46, 81.6)
  line L61 (44.4, 80) -> (44.4, 46)
  line L62 (46, 44.4) -> (80, 44.4)
  line L63 (81.6, 46) -> (81.6, 80)
  arc A60 (46, 81.6) -> (44.4, 80) centre (46, 80) ccw
  arc A61 (44.4, 46) -> (46, 44.4) centre (46, 46) ccw
  arc A62 (80, 44.4) -> (81.6, 46) centre (80, 46) ccw
  arc A63 (81.6, 80) -> (80, 81.6) centre (80, 80) ccw
  constraint tangent L0 A0
  constraint tangent L1 A0
  constraint tangent L1 A1
  constraint tangent L2 A1
  constraint tangent L2 A2
  constraint tangent L3 A2
  constraint tangent L3 A3
  constraint tangent L0 A3
  constraint tangent L4 A4
  constraint tangent L5 A4
  constraint tangent L5 A5
  constraint tangent L6 A5
  constraint tangent L6 A6
  constraint tangent L7 A6
  constraint tangent L7 A7
  constraint tangent L4 A7
  constraint tangent L8 A8
  constraint tangent L9 A8
  constraint tangent L9 A9
  constraint tangent L10 A9
  constraint tangent L10 A10
  constraint tangent L11 A10
  constraint tangent L11 A11
  constraint tangent L8 A11
  constraint tangent L12 A12
  constraint tangent L13 A12
  constraint tangent L13 A13
  constraint tangent L14 A13
  constraint tangent L14 A14
  constraint tangent L15 A14
  constraint tangent L15 A15
  constraint tangent L12 A15
  constraint tangent L16 A16
  constraint tangent L17 A16
  constraint tangent L17 A17
  constraint tangent L18 A17
  constraint tangent L18 A18
  constraint tangent L19 A18
  constraint tangent L19 A19
  constraint tangent L16 A19
  constraint tangent L20 A20
  constraint tangent L21 A20
  constraint tangent L21 A21
  constraint tangent L22 A21
  constraint tangent L22 A22
  constraint tangent L23 A22
  constraint tangent L23 A23
  constraint tangent L20 A23
  constraint tangent L24 A24
  constraint tangent L25 A24
  constraint tangent L25 A25
  constraint tangent L26 A25
  constraint tangent L26 A26
  constraint tangent L27 A26
  constraint tangent L27 A27
  constraint tangent L24 A27
  constraint tangent L28 A28
  constraint tangent L29 A28
  constraint tangent L29 A29
  constraint tangent L30 A29
  constraint tangent L30 A30
  constraint tangent L31 A30
  constraint tangent L31 A31
  constraint tangent L28 A31
  constraint tangent L32 A32
  constraint tangent L33 A32
  constraint tangent L33 A33
  constraint tangent L34 A33
  constraint tangent L34 A34
  constraint tangent L35 A34
  constraint tangent L35 A35
  constraint tangent L32 A35
  constraint tangent L36 A36
  constraint tangent L37 A36
  constraint tangent L37 A37
  constraint tangent L38 A37
  constraint tangent L38 A38
  constraint tangent L39 A38
  constraint tangent L39 A39
  constraint tangent L36 A39
  constraint tangent L40 A40
  constraint tangent L41 A40
  constraint tangent L41 A41
  constraint tangent L42 A41
  constraint tangent L42 A42
  constraint tangent L43 A42
  constraint tangent L43 A43
  constraint tangent L40 A43
  constraint tangent L44 A44
  constraint tangent L45 A44
  constraint tangent L45 A45
  constraint tangent L46 A45
  constraint tangent L46 A46
  constraint tangent L47 A46
  constraint tangent L47 A47
  constraint tangent L44 A47
  constraint tangent L48 A48
  constraint tangent L49 A48
  constraint tangent L49 A49
  constraint tangent L50 A49
  constraint tangent L50 A50
  constraint tangent L51 A50
  constraint tangent L51 A51
  constraint tangent L48 A51
  constraint tangent L52 A52
  constraint tangent L53 A52
  constraint tangent L53 A53
  constraint tangent L54 A53
  constraint tangent L54 A54
  constraint tangent L55 A54
  constraint tangent L55 A55
  constraint tangent L52 A55
  constraint tangent L56 A56
  constraint tangent L57 A56
  constraint tangent L57 A57
  constraint tangent L58 A57
  constraint tangent L58 A58
  constraint tangent L59 A58
  constraint tangent L59 A59
  constraint tangent L56 A59
  constraint tangent L60 A60
  constraint tangent L61 A60
  constraint tangent L61 A61
  constraint tangent L62 A61
  constraint tangent L62 A62
  constraint tangent L63 A62
  constraint tangent L63 A63
  constraint tangent L60 A63
extrude "gf_std_foot3 (1)" add sketch "gf_std_foot3" against normal blind 0.8 draft -45 bodies 1 in component "drop_plate"
ref_plane "WorkPlane5" through (0, 0, 7.25) normal (0, 0, 1) x (1, 0, 0) in component "drop_plate"